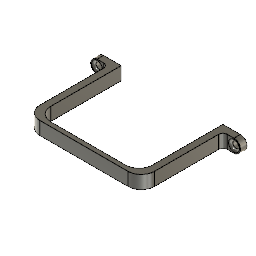
koppla_mount (Autodesk Fusion 360 design; units mm, degrees)
Autodesk Fusion 360 part; units mm, degrees
sketch "Sketch1" plane through (0, 0, 0) normal (0, 0, 1) x (1, 0, 0)
  line L0 (0, 0) -> (-26, 0)
  line L1 (-26, 0) -> (-26, 37)
  line L2 (-26, 37) -> (-34, 37)
  line L3 (-34, 37) -> (-34, 40)
  line L4 (-34, 40) -> (-23, 40)
  line L5 (-23, 40) -> (-23, 2)
  line L6 (-23, 2) -> (0, 2)
  line L7 (0, 2) -> (0, 0)
  line L8 (0, 2.5) -> (0, 20)
  line L9 (26, 37) -> (34, 37)
  line L10 (34, 37) -> (34, 40)
  line L11 (34, 40) -> (23, 40)
  line L12 (23, 40) -> (23, 2)
  line L13 (23, 2) -> (0, 2)
  line L14 (0, 0) -> (26, 0)
  line L15 (0, 2) -> (0, 0)
  line L16 (26, 0) -> (26, 37)
  dimension "d1" = 3
  dimension "d2" = 3
  dimension "d3" = 2
  dimension "d4" = 38
  dimension "d5" = 23
  dimension "d6" = 8
  constraint coincident L0.start L7.end
  constraint horizontal L0
  constraint perpendicular L0 L1
  constraint perpendicular L1 L2
  constraint perpendicular L0 L3
  constraint perpendicular L3 L4
  constraint perpendicular L4 L5
  constraint perpendicular L3 L6
  constraint vertical L7
  constraint symmetric L0.start L8 L7.end
  constraint symmetric L0.end L8 L14.end
  constraint symmetric L1.end L8 L9.start
  constraint symmetric L2.end L8 L9.end
  constraint symmetric L3.end L8 L10.end
  constraint symmetric L4.end L8 L11.end
  constraint symmetric L5.end L8 L12.end
  constraint symmetric L6.end L8 L7.start
  measures "d1" distance of L2 L4
  measures "d2" distance of L1 L5
  measures "d3" distance of L0 L6
  measures "d4" distance of L4 L6
  measures "d5" distance of L5 L6.end
  measures "d6" distance of L1.end L2.end
extrude "Extrude1" add sketch "Sketch1" along normal blind 6
sketch "Sketch2" plane through (0, 40, 0) normal (0, 1, 0) x (-1, 0, 0)
  line L0 (23, 0) -> (34, 0)
  line L1 (34, 0) -> (34, 6)
  line L2 (34, 6) -> (23, 6)
  line L3 (23, 6) -> (23, 0)
  circle A0 centre (-31, 3) radius 1.5
  line L4 (0, 20) -> (0, 2.5)
  circle A1 centre (31, 3) radius 1.5
  line L5 (-34, 0) -> (-34, 6)
  dimension "d9" = 3
  dimension "d10" = 3
  constraint symmetric A0 L4 A1
  measures "d9" diameter of A0
  measures "d10" distance of A0.centre L5
extrude "Extrude2" cut sketch "Sketch2" against normal through all contours A0 | A1
fillet "Fillet1" radius 3 4 edges at (34, 38.5, 6) (34, 38.5, 0) (-34, 38.5, 6) (-34, 38.5, 0)
fillet "Fillet2" radius 6 4 edges at (-26, 0, 3) (26, 0, 3) (-23, 2, 3) (23, 2, 3)
fillet "Fillet3" radius 1 2 edges at (32.3985, 37, 2.4576) (-29.6015, 37, 2.4576)
fillet "Fillet4" radius 2 2 edges at (26, 37, 3) (-26, 37, 3)
equation "d5 = ( 46 / 2 ) * 1 mm"
